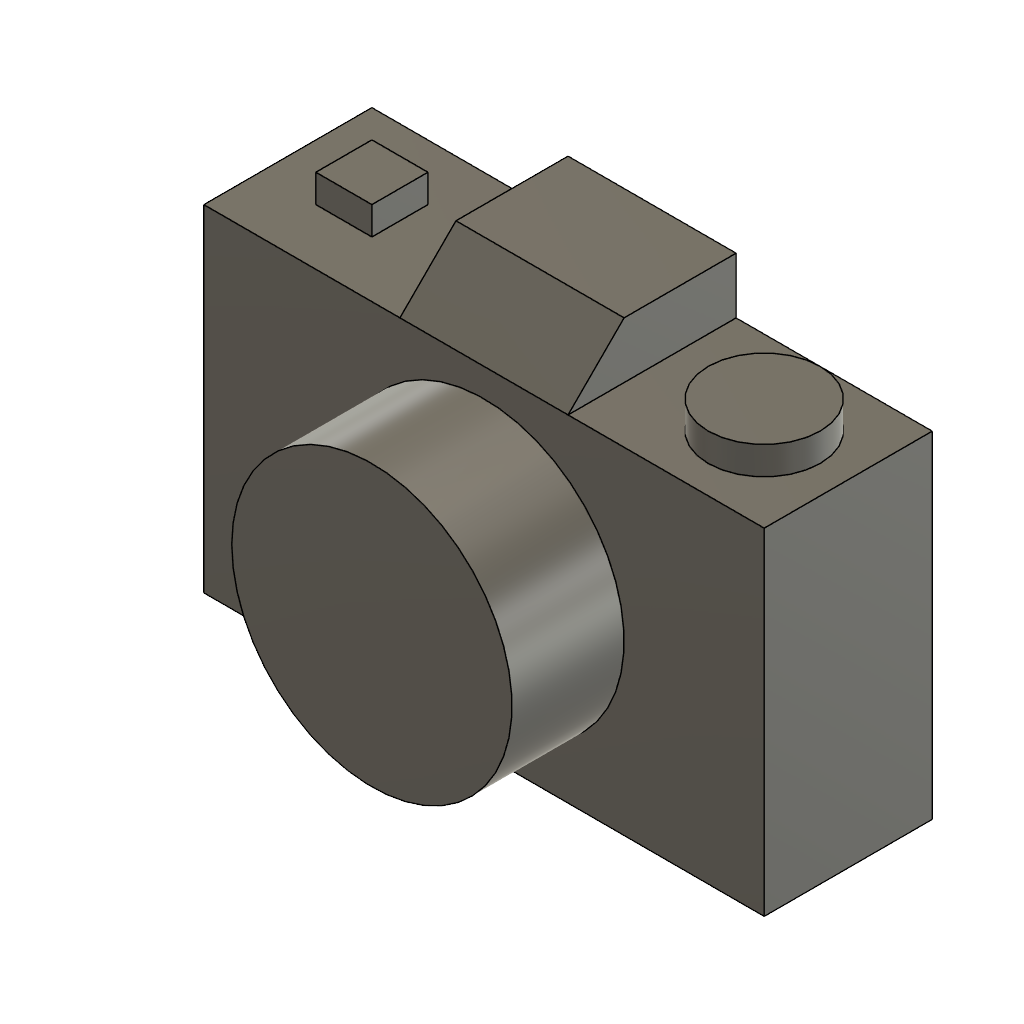
Ex 2.1 (Autodesk Fusion 360 design; units mm, degrees)
part number: 2026-10-13-15-30-29-154
Autodesk Fusion 360 part; units mm, degrees
sketch "Sketch1" plane through (0, 0, 0) normal (0, 0, 1) x (1, 0, 0)
  line L0 (-50, 30) -> (50, 30)
  line L1 (50, 30) -> (50, -30)
  line L2 (50, -30) -> (-50, -30)
  line L3 (-50, -30) -> (-50, 30)
  line L4 (-50, 30) -> (50, -30) construction
  line L5 (50, 30) -> (-50, -30) construction
  constraint horizontal L0
  constraint perpendicular L0 L1
  constraint parallel L0 L2
  constraint parallel L1 L3
  constraint coincident L4 origin
  constraint coincident L5 origin
extrude "Extrude1" add sketch "Sketch1" along normal blind 30
sketch "Sketch2" plane through (0, 0, 30) normal (0, 0, 1) x (1, 0, 0)
  line L0 (-50, -30) -> (50, -30)
  line L1 (50, -30) -> (50, 30)
  line L2 (50, 30) -> (-50, 30)
  line L3 (-50, 30) -> (-50, -30)
  circle A0 centre (0, 0) radius 25
  dimension "d4" = 50
  constraint coincident A0.centre origin
  measures "d4" diameter of A0
extrude "Extrude2" add sketch "Sketch2" along normal blind 20 contours A0
sketch "Sketch3" plane through (0, 30, 0) normal (0, 1, 0) x (-1, 0, 0)
  line L0 (-50, 0) -> (50, 0)
  line L1 (50, 0) -> (50, 30)
  line L2 (50, 30) -> (-50, 30)
  line L3 (-50, 30) -> (-50, 0)
  circle A0 centre (-35, 15) radius 10
  dimension "d7" = 20
  measures "d7" diameter of A0
extrude "Extrude3" add sketch "Sketch3" along normal blind 5 contours A0
sketch "Sketch4" plane through (0, 30, 0) normal (0, 1, 0) x (-1, 0, 0)
  circle A0 centre (-35, 15) radius 10
  line L0 (-50, 0) -> (50, 0)
  line L1 (50, 0) -> (50, 30)
  line L2 (50, 30) -> (-50, 30)
  line L3 (-50, 30) -> (-50, 0)
  line L4 (-50, -15) -> (-15, -15)
  line L5 (-15, 0) -> (15, 0)
  line L6 (15, 0) -> (15, 20)
  line L7 (15, 20) -> (-15, 20)
  line L8 (-15, 20) -> (-15, 0)
  constraint horizontal L4
  constraint horizontal L5
  constraint vertical L6
  constraint horizontal L7
  constraint vertical L8
  constraint coincident L0 L5.start
extrude "Extrude4" add sketch "Sketch4" along normal blind 10 contours L0 L5 L6 L7 L8
draft "Draft1" angle 45 neutral plane through (0, 40, 0) pull (0, 1, 0) 1 faces at (-5, 33.3333, 20)
sketch "Sketch5" plane through (0, 30, 0) normal (0, 1, 0) x (-1, 0, 0)
  line L0 (50, 30) -> (15, 30)
  line L1 (15, 30) -> (15, 0)
  line L2 (15, 0) -> (50, 0)
  line L3 (50, 0) -> (50, 30)
  line L4 (-50, -15) -> (19, -32)
  line L5 (40, 10) -> (30, 10)
  line L6 (30, 10) -> (30, 20)
  line L7 (30, 20) -> (40, 20)
  line L8 (40, 20) -> (40, 10)
  constraint horizontal L5
  constraint vertical L6
  constraint horizontal L7
  constraint vertical L8
extrude "Extrude5" add sketch "Sketch5" along normal blind 5 contours L5 L6 L7 L8
